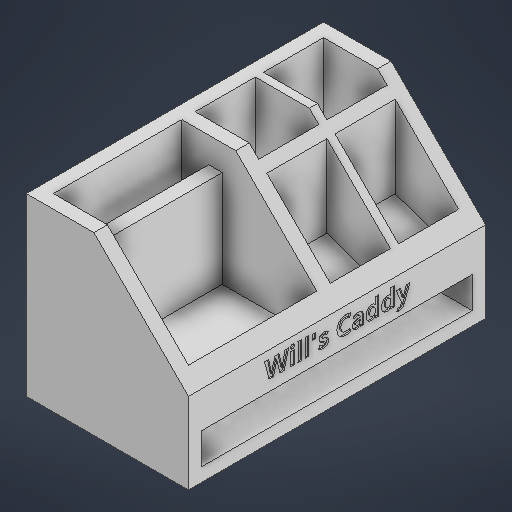
# Autodesk Inventor part: oldcaddy
Saved by Autodesk Inventor 2027.1 (Build 311270010, 270A)
## iProperties
Created: 2026-09-24
Part Number: oldcaddy
Material: Generic
Document SubType Name: Modeling
Designer: wh29971
Density: 1 g/cm^3
Appearance: Default
Author: wh29971
Autodesk Inventor part; units mm, degrees
ref_plane "YZ Plane" through (0, 0, 0) normal (1, 0, 0) x (0, 1, 0)
ref_plane "XZ Plane" through (0, 0, 0) normal (0, 1, 0) x (-1, 0, 0)
ref_plane "XY Plane" through (0, 0, 0) normal (0, 0, 1) x (1, 0, 0)
sketch "Sketch1" plane through (0, 0, 0) normal (0, 1, 0) x (-1, 0, 0)
  line L0 (-60, -110) -> (60, -110)
  line L1 (60, -110) -> (60, 110)
  line L2 (60, 110) -> (-60, 110)
  line L3 (-60, 110) -> (-60, -110)
  line L4 (-60, -110) -> (60, 110) construction
  line L5 (60, -110) -> (-60, 110) construction
  point P0 (0, 0)
  dimension "d0" = 120
  dimension "d1" = 220
  constraints: 12 end point, 2 midpoint, 2 parallel, 1 horizontal, 1 perpendicular
  measures "d0" distance of L1.end L2.end
  measures "d1" distance of L2.end L0.start
extrude "Extrusion1" add sketch "Sketch1" along normal blind 10
sketch "Sketch2" plane through (0, 10, 0) normal (0, 1, 0) x (1, 0, 0)
  point P0 (0, 0)
sketch "Sketch3" plane through (0, 10, 0) normal (0, 1, 0) x (1, 0, 0)
  line L0 (-60, 110) -> (-60, -110) projected
  line L1 (60, -110) -> (60, 110) projected
  line L2 (60, 100) -> (-50, 100)
  line L3 (-50, 100) -> (-50, -100)
  line L4 (-50, -100) -> (60, -100)
  line L5 (60, -100) -> (60, -110)
  line L6 (-60, -110) -> (60, -110) projected
  line L7 (-50, -100) -> (-50, -110)
  line L8 (-50, 100) -> (-50, 110)
  line L9 (60, 110) -> (-60, 110) projected
  point P0 (0, 0)
  dimension "d4" = 10
  dimension "d5" = 10
  constraints: 12 end point, 4 point on line, 3 perpendicular, 2 vertical, 1 collinear, 1 horizontal
  measures "d4" distance between parallel lines of L0 L3
  measures "d5" distance between parallel lines of L6 L4
extrude "Extrusion2" add sketch "Sketch3" along normal blind 120 contours L9 L8 L3 L7 L6 L0 | L9 L1 L2 L8 | L7 L4 L1 L6
chamfer "Chamfer1" distance 70 angle 45 2 edges at (60, 130, 105) (60, 130, -105)
sketch "Sketch4" plane through (-50, 10, 100) normal (1, 0, 0) x (0, 0, -1)
  line L0 (200, 0) -> (200, 50) projected
  line L1 (200, 29.3572) -> (0, 29.3572)
  line L2 (0, 0) -> (0, 50) projected
  line L3 (0, 23.1542) -> (200, 23.1542)
  point P0 (100, -10)
  constraints: 4 end point, 4 point on line, 1 horizontal, 1 perpendicular
extrude "Extrusion3" add sketch "Sketch4" along normal up to surface (110 mm away)
sketch "Sketch5" plane through (-50, 39.3572, 100) normal (0, 1, 0) x (1, 0, 0)
  line L0 (0, 0) -> (110, 0) projected
  line L1 (100, 0) -> (100, 200)
  line L2 (40, 200) -> (110, 200) projected
  line L3 (110, 0) -> (110, 200) projected
  point P0 (50, 100)
  dimension "d13" = 10
  constraints: 2 end point, 2 point on line, 1 vertical
  measures "d13" distance between parallel lines of L3 L1
extrude "Extrusion4" add sketch "Sketch5" along normal up to surface (20.6428 mm away)
sketch "Sketch6" plane through (-10, 130, 100) normal (0, 0, -1) x (-1, 0, 0)
  line L0 (-60, -70) -> (-60, -60)
  line L1 (-70, -70) -> (0, 0) projected
  line L2 (-60, -60) -> (-70, -70)
  line L3 (-70, -70) -> (-60, -70) projected
  line L4 (-70, -70) -> (-60, -70)
  point P0 (-10, -130)
  constraints: 6 end point, 1 collinear, 1 horizontal, 1 point on line, 1 vertical
extrude "Extrusion5" add sketch "Sketch6" along normal up to surface (200 mm away)
sketch "Sketch7" plane through (-50, 39.3572, 100) normal (0, 1, 0) x (1, 0, 0)
  line L0 (0, 0) -> (0, 200) projected
  line L1 (0, 100) -> (100, 100)
  line L2 (0, 95) -> (100, 95)
  line L3 (100, 0) -> (100, 200) projected
  line L4 (0, 105) -> (100, 105)
  line L5 (100, 0) -> (100, 200) projected
  line L6 (100, 95) -> (100, 100)
  line L7 (100, 100) -> (100, 105)
  line L8 (100, 95) -> (100, 100)
  point P0 (50, 100)
  dimension "d19" = 10
  constraints: 12 end point, 4 point on line, 3 collinear, 3 perpendicular, 2 horizontal, 1 midpoint, 1 other
  measures "d19" diameter of L4 L1
extrude "Extrusion6" add sketch "Sketch7" along normal up to surface (90.6428 mm away)
sketch "Sketch8" plane through (-50, 39.3572, 5) normal (0, 0, 1) x (1, 0, 0)
  line L0 (40, 90.6428) -> (110, 20.6428) projected
  line L1 (40, 90.6428) -> (110, 20.6428)
  line L2 (0, 90.6428) -> (100, 90.6428) projected
  line L3 (100, 30.6428) -> (100, 90.6428)
  line L4 (100, 90.6428) -> (40, 90.6428)
  point P0 (50, -39.3572)
  constraints: 6 end point, 1 collinear, 1 perpendicular, 1 point on line, 1 vertical
extrude "Extrusion7" cut sketch "Sketch8" against normal blind 10
sketch "Sketch9" plane through (-50, 39.3572, -100) normal (0, 1, 0) x (1, 0, 0)
  line L0 (100, -105) -> (0, -105) projected
  line L1 (30, -200) -> (30, -103.9519)
  line L2 (100, -200) -> (0, -200) projected
  line L3 (20, -200) -> (20, -103.3004)
  line L4 (20, -105) -> (30, -105)
  line L5 (20, -200) -> (30, -200)
  line L6 (0, -200) -> (0, -105) projected
  point P0 (50, -100)
  dimension "d25" = 10
  dimension "d26" = 20
  constraints: 8 end point, 5 point on line, 2 perpendicular, 1 parallel
  measures "d25" distance between parallel lines of L3 L1
  measures "d26" distance between parallel lines of L6 L3
extrude "Extrusion8" add sketch "Sketch9" along normal blind 71.643 contours L0 L1 L2 L3
sketch "Sketch13" plane through (-50, 39.3572, -100) normal (0, 1, 0) x (1, 0, 0)
  line L0 (0, 0) -> (0, -200) projected
  line L1 (0, -50.5) -> (47, -50.5)
  line L2 (100, -95) -> (100, 0) projected
  line L3 (47, -50.5) -> (47, -95)
  line L4 (40, -95) -> (100, -95) projected
  line L5 (53, -95) -> (53, -50.5)
  line L6 (53, -50.5) -> (100, -50.5)
  line L7 (100, -44.5) -> (53, -44.5)
  line L8 (53, -44.5) -> (53, 0)
  line L9 (47, -44.5) -> (47, 0)
  line L10 (110, 0) -> (0, 0) projected
  line L11 (47, -44.5) -> (0, -44.5)
  line L12 (53, -50.5) -> (53, -44.5) construction
  line L13 (0, -95) -> (0, 0) projected
  line L14 (0, -47.5) -> (100, -47.5)
  line L15 (47, -47.5) -> (47, -44.5) construction
  line L16 (47, -47.5) -> (47, -50.5) construction
  line L17 (0, -95) -> (100, -95) projected
  line L18 (50, -95) -> (50, 0) construction
  line L19 (40, 0) -> (100, 0) projected
  line L20 (47, -50.5) -> (50, -50.5) construction
  line L21 (50, -50.5) -> (53, -50.5) construction
  point P0 (50, -100)
  point P1 (0, -44.5)
  dimension "d39" = 3
  dimension "d40" = 3
  dimension "d41" = 47.5
  constraints: 30 end point, 9 perpendicular, 8 point on line, 6 equal length, 5 vertical, 3 horizontal, 3 midpoint
  measures "d39" distance between parallel lines of L14 L1
  measures "d40" distance of L20.end L5.end
  measures "d41" distance between parallel lines of L17 L14
extrude "Extrusion11" add sketch "Sketch13" along normal up to surface (90.6428 mm away) contours L11 L9 L10 L8 L7 L2 L14 L0 | L14 L2 L6 L5 L4 L3 L1 L0
sketch "Sketch15" plane through (60, 0, -110) normal (0, 0, -1) x (-1, 0, 0)
  line L0 (70, 130) -> (0, 130)
  line L1 (0, 130) -> (0, 60)
  line L2 (0, 60) -> (70, 130)
  line L3 (0, 60) -> (70, 130) projected
  point P0 (60, 0)
  constraints: 6 end point, 1 collinear, 1 horizontal, 1 perpendicular
extrude "Extrusion12" cut sketch "Sketch15" against normal up to surface (115 mm away)
sketch "Sketch16" plane through (50, 39.3572, -5) normal (0, 0, -1) x (-1, 0, 0)
  line L0 (47, 0) -> (0, 0) projected
  line L1 (0, 0) -> (100, 36.397)
  line L2 (100, 90.6428) -> (100, 0) projected
  line L3 (100, 36.397) -> (100, 0)
  line L4 (100, 0) -> (0, 0)
  point P0 (50, -39.3572)
  point P1 (47, 0)
  dimension "d47" = 20
  constraints: 6 end point, 2 collinear, 1 point on line
  measures "d47" angle of L0 L1
extrude "Extrusion13" add sketch "Sketch16" along normal up to surface (95 mm away)
sketch "Sketch17" plane through (60, 0, 110) normal (1, 0, 0) x (0, 0, -1)
  line L0 (30, 55) -> (190, 55) construction
  line L1 (190, 55) -> (190, 38.1542) construction
  line L2 (190, 38.1542) -> (30, 38.1542) construction
  line L3 (30, 38.1542) -> (30, 55) construction
  line L4 (0, 60) -> (220, 60) projected
  line L5 (210, 33.1542) -> (10, 33.1542) projected
  line L6 (190, 38.1542) -> (220, 38.1542) construction
  line L7 (220, 0) -> (220, 130) projected
  line L8 (30, 38.1542) -> (0, 38.1542) construction
  line L9 (0, 0) -> (0, 60) projected
  line L10 (74.1796, 53.8926) -> (70.7985, 41.1926)
  line L11 (70.7985, 41.1926) -> (67.7354, 41.1926)
  line L12 (67.7354, 41.1926) -> (65.5912, 49.4158)
  spline S0 degree 2 poles (65.5912, 49.4158) (65.5088, 49.7339) (65.4027, 50.4525) (65.3792, 50.8413) knots 0 0 0 1 2 2 2
  line L13 (65.3792, 50.8413) -> (65.3438, 50.8413)
  spline S1 degree 2 poles (65.3438, 50.8413) (65.3085, 50.4172) (65.2025, 49.6985) (65.12, 49.4158) knots 0 0 0 1 2 2 2
  line L14 (65.12, 49.4158) -> (62.9169, 41.1926)
  line L15 (62.9169, 41.1926) -> (59.7243, 41.1926)
  line L16 (59.7243, 41.1926) -> (56.3549, 53.8926)
  line L17 (56.3549, 53.8926) -> (59.3826, 53.8926)
  line L18 (59.3826, 53.8926) -> (61.2322, 45.3513)
  spline S2 degree 2 poles (61.2322, 45.3513) (61.3029, 45.0686) (61.3736, 44.3499) (61.409, 43.9022) knots 0 0 0 1 2 2 2
  line L19 (61.409, 43.9022) -> (61.4561, 43.9022)
  spline S3 degree 2 poles (61.4561, 43.9022) (61.4796, 44.2439) (61.6092, 44.9861) (61.7153, 45.3866) knots 0 0 0 1 2 2 2
  line L20 (61.7153, 45.3866) -> (64.0597, 53.8926)
  line L21 (64.0597, 53.8926) -> (67.0167, 53.8926)
  line L22 (67.0167, 53.8926) -> (69.1256, 45.2806)
  spline S4 degree 2 poles (69.1256, 45.2806) (69.1845, 45.045) (69.2905, 44.3617) (69.3376, 43.9258) knots 0 0 0 1 2 2 2
  line L23 (69.3376, 43.9258) -> (69.373, 43.9258)
  spline S5 degree 2 poles (69.373, 43.9258) (69.3847, 44.2674) (69.4908, 44.9625) (69.5615, 45.3277) knots 0 0 0 1 2 2 2
  line L24 (69.5615, 45.3277) -> (71.3757, 53.8926)
  line L25 (71.3757, 53.8926) -> (74.1796, 53.8926)
  line L26 (78.4208, 41.1926) -> (75.723, 41.1926)
  line L27 (75.723, 41.1926) -> (75.723, 50.7588)
  line L28 (75.723, 50.7588) -> (78.4208, 50.7588)
  line L29 (78.4208, 50.7588) -> (78.4208, 41.1926)
  spline S6 degree 2 poles (77.0896, 52.0076) (76.3827, 52.0076) (75.4756, 52.8676) (75.4756, 53.5038) knots 0 0 0 1 2 2 2
  spline S7 degree 2 poles (75.4756, 53.5038) (75.4756, 54.1635) (76.3827, 55) (77.0896, 55) knots 0 0 0 1 2 2 2
  spline S8 degree 2 poles (77.0896, 55) (77.8082, 55) (78.6918, 54.1635) (78.6918, 53.5038) knots 0 0 0 1 2 2 2
  spline S9 degree 2 poles (78.6918, 53.5038) (78.6918, 52.8441) (77.8082, 52.0076) (77.0896, 52.0076) knots 0 0 0 1 2 2 2
  line L30 (81.1187, 41.1926) -> (81.1187, 54.623)
  line L31 (81.1187, 54.623) -> (83.8283, 54.623)
  line L32 (83.8283, 54.623) -> (83.8283, 41.1926)
  line L33 (83.8283, 41.1926) -> (81.1187, 41.1926)
  line L34 (86.3966, 41.1926) -> (86.3966, 54.623)
  line L35 (86.3966, 54.623) -> (89.1063, 54.623)
  line L36 (89.1063, 54.623) -> (89.1063, 41.1926)
  line L37 (89.1063, 41.1926) -> (86.3966, 41.1926)
  line L38 (94.0897, 49.9813) -> (92.0162, 49.9813)
  line L39 (92.0162, 49.9813) -> (92.0162, 53.8808)
  line L40 (92.0162, 53.8808) -> (94.0897, 53.8926)
  line L41 (94.0897, 53.8926) -> (94.0897, 49.9813)
  line L42 (96.2103, 42.0055) -> (97.3295, 43.8787)
  spline S10 degree 2 poles (97.3295, 43.8787) (97.8007, 43.4781) (99.0848, 42.9244) (99.8624, 42.9244) knots 0 0 0 1 2 2 2
  spline S11 degree 2 poles (99.8624, 42.9244) (100.4632, 42.9244) (101.2054, 43.3956) (101.2054, 43.8904) knots 0 0 0 1 2 2 2
  spline S12 degree 2 poles (101.2054, 43.8904) (101.2054, 44.2557) (100.6282, 44.6916) (99.8388, 44.8565) knots 0 0 0 1 2 2 2
  spline S13 degree 2 poles (99.8388, 44.8565) (98.107, 45.2453) (96.599, 46.6119) (96.599, 47.8489) knots 0 0 0 1 2 2 2
  spline S14 degree 2 poles (96.599, 47.8489) (96.599, 49.2862) (98.8256, 50.9944) (100.4514, 50.9944) knots 0 0 0 1 2 2 2
  spline S15 degree 2 poles (100.4514, 50.9944) (101.2879, 50.9944) (102.7723, 50.5585) (103.4321, 50.1109) knots 0 0 0 1 2 2 2
  line L43 (103.4321, 50.1109) -> (102.4189, 48.379)
  spline S16 degree 2 poles (102.4189, 48.379) (101.8534, 48.7325) (100.8756, 49.0623) (100.3572, 49.0623) knots 0 0 0 1 2 2 2
  spline S17 degree 2 poles (100.3572, 49.0623) (99.7446, 49.0623) (99.0141, 48.5558) (99.0141, 48.167) knots 0 0 0 1 2 2 2
  spline S18 degree 2 poles (99.0141, 48.167) (99.0141, 47.7546) (99.6739, 47.3659) (100.6164, 47.1656) knots 0 0 0 1 2 2 2
  spline S19 degree 2 poles (100.6164, 47.1656) (102.2186, 46.8239) (103.6323, 45.4102) (103.6323, 44.185) knots 0 0 0 1 2 2 2
  spline S20 degree 2 poles (103.6323, 44.185) (103.6323, 42.7359) (101.5, 40.9805) (99.7446, 40.9805) knots 0 0 0 1 2 2 2
  spline S21 degree 2 poles (99.7446, 40.9805) (98.7903, 40.9805) (97.0585, 41.4871) (96.2103, 42.0055) knots 0 0 0 1 2 2 2
  spline S22 degree 2 poles (120.2083, 41.8641) (119.2069, 41.4046) (117.3219, 40.9805) (116.2263, 40.9805) knots 0 0 0 1 2 2 2
  spline S23 degree 2 poles (116.2263, 40.9805) (113.2692, 40.9805) (109.8645, 44.3028) (109.8645, 47.3894) knots 0 0 0 1 2 2 2
  spline S24 degree 2 poles (109.8645, 47.3894) (109.8645, 50.2876) (113.5756, 54.1046) (116.6151, 54.1046) knots 0 0 0 1 2 2 2
  spline S25 degree 2 poles (116.6151, 54.1046) (117.64, 54.1046) (119.2658, 53.7983) (120.1258, 53.4567) knots 0 0 0 1 2 2 2
  line L44 (120.1258, 53.4567) -> (119.2658, 51.2301)
  spline S26 degree 2 poles (119.2658, 51.2301) (118.6296, 51.4892) (117.4044, 51.7249) (116.6975, 51.7249) knots 0 0 0 1 2 2 2
  spline S27 degree 2 poles (116.6975, 51.7249) (115.0953, 51.7249) (112.7744, 49.4865) (112.7744, 47.5897) knots 0 0 0 1 2 2 2
  spline S28 degree 2 poles (112.7744, 47.5897) (112.7744, 45.6223) (114.8126, 43.4074) (116.568, 43.4074) knots 0 0 0 1 2 2 2
  spline S29 degree 2 poles (116.568, 43.4074) (117.0745, 43.4074) (118.4647, 43.7255) (119.1951, 44.0789) knots 0 0 0 1 2 2 2
  line L45 (119.1951, 44.0789) -> (120.2083, 41.8641)
  line L46 (129.5978, 41.1926) -> (127.0295, 41.1926)
  line L47 (127.0295, 41.1926) -> (127.0295, 42.5945)
  line L48 (127.0295, 42.5945) -> (126.9942, 42.5945)
  spline S30 degree 2 poles (126.9942, 42.5945) (126.5347, 41.7934) (125.1328, 40.9805) (124.2492, 40.9805) knots 0 0 0 1 2 2 2
  spline S31 degree 2 poles (124.2492, 40.9805) (123.0004, 40.9805) (121.3039, 42.5003) (121.3039, 43.8551) knots 0 0 0 1 2 2 2
  spline S32 degree 2 poles (121.3039, 43.8551) (121.3039, 45.1864) (123.0004, 46.8475) (124.7676, 47.0949) knots 0 0 0 1 2 2 2
  line L49 (124.7676, 47.0949) -> (127.0531, 47.413)
  line L50 (127.0531, 47.413) -> (127.0531, 47.6015)
  spline S33 degree 2 poles (127.0531, 47.6015) (127.0531, 48.3555) (126.1695, 49.1212) (125.392, 49.1212) knots 0 0 0 1 2 2 2
  spline S34 degree 2 poles (125.392, 49.1212) (124.7911, 49.1212) (123.4245, 48.7207) (122.7295, 48.2848) knots 0 0 0 1 2 2 2
  line L51 (122.7295, 48.2848) -> (121.7634, 49.8635)
  spline S35 degree 2 poles (121.7634, 49.8635) (122.6705, 50.4525) (124.5437, 50.9944) (125.6394, 50.9944) knots 0 0 0 1 2 2 2
  spline S36 degree 2 poles (125.6394, 50.9944) (127.6657, 50.9944) (129.5978, 48.9917) (129.5978, 46.9653) knots 0 0 0 1 2 2 2
  line L52 (129.5978, 46.9653) -> (129.5978, 41.1926)
  line L53 (127.0531, 45.1157) -> (127.0531, 45.8225)
  line L54 (127.0531, 45.8225) -> (125.2859, 45.5869)
  spline S37 degree 2 poles (125.2859, 45.5869) (124.5437, 45.4691) (123.8133, 44.7622) (123.8133, 44.1732) knots 0 0 0 1 2 2 2
  spline S38 degree 2 poles (123.8133, 44.1732) (123.8133, 43.6195) (124.532, 42.9244) (125.1328, 42.9244) knots 0 0 0 1 2 2 2
  spline S39 degree 2 poles (125.1328, 42.9244) (125.981, 42.9244) (127.0531, 44.1732) (127.0531, 45.1157) knots 0 0 0 1 2 2 2
  spline S40 degree 2 poles (138.2569, 42.5592) (137.7621, 41.7699) (136.313, 40.9805) (135.347, 40.9805) knots 0 0 0 1 2 2 2
  spline S41 degree 2 poles (135.347, 40.9805) (133.6152, 40.9805) (131.471, 43.5135) (131.471, 45.7636) knots 0 0 0 1 2 2 2
  spline S42 degree 2 poles (131.471, 45.7636) (131.471, 48.1316) (133.8272, 50.9944) (135.724, 50.9944) knots 0 0 0 1 2 2 2
  spline S43 degree 2 poles (135.724, 50.9944) (136.6311, 50.9944) (137.9035, 50.3229) (138.2569, 49.6514) knots 0 0 0 1 2 2 2
  line L55 (138.2569, 49.6514) -> (138.2923, 49.6514)
  line L56 (138.2923, 49.6514) -> (138.2923, 54.623)
  line L57 (138.2923, 54.623) -> (141.0137, 54.623)
  line L58 (141.0137, 54.623) -> (141.0137, 41.1926)
  line L59 (141.0137, 41.1926) -> (138.2923, 41.1926)
  line L60 (138.2923, 41.1926) -> (138.2923, 42.5592)
  line L61 (138.2923, 42.5592) -> (138.2569, 42.5592)
  spline S44 degree 2 poles (134.2278, 45.8579) (134.2278, 44.5266) (135.3234, 43.0658) (136.2777, 43.0658) knots 0 0 0 1 2 2 2
  spline S45 degree 2 poles (136.2777, 43.0658) (137.1966, 43.0658) (138.3512, 44.5855) (138.3512, 45.8108) knots 0 0 0 1 2 2 2
  line L62 (138.3512, 45.8108) -> (138.3512, 46.6354)
  spline S46 degree 2 poles (138.3512, 46.6354) (138.3512, 47.6133) (137.2437, 48.9092) (136.3602, 48.9092) knots 0 0 0 1 2 2 2
  spline S47 degree 2 poles (136.3602, 48.9092) (135.3705, 48.9092) (134.2278, 47.2834) (134.2278, 45.8579) knots 0 0 0 1 2 2 2
  spline S48 degree 2 poles (149.8024, 42.5592) (149.3076, 41.7699) (147.8585, 40.9805) (146.8924, 40.9805) knots 0 0 0 1 2 2 2
  spline S49 degree 2 poles (146.8924, 40.9805) (145.1606, 40.9805) (143.0165, 43.5135) (143.0165, 45.7636) knots 0 0 0 1 2 2 2
  spline S50 degree 2 poles (143.0165, 45.7636) (143.0165, 48.1316) (145.3727, 50.9944) (147.2694, 50.9944) knots 0 0 0 1 2 2 2
  spline S51 degree 2 poles (147.2694, 50.9944) (148.1766, 50.9944) (149.4489, 50.3229) (149.8024, 49.6514) knots 0 0 0 1 2 2 2
  line L63 (149.8024, 49.6514) -> (149.8377, 49.6514)
  line L64 (149.8377, 49.6514) -> (149.8377, 54.623)
  line L65 (149.8377, 54.623) -> (152.5591, 54.623)
  line L66 (152.5591, 54.623) -> (152.5591, 41.1926)
  line L67 (152.5591, 41.1926) -> (149.8377, 41.1926)
  line L68 (149.8377, 41.1926) -> (149.8377, 42.5592)
  line L69 (149.8377, 42.5592) -> (149.8024, 42.5592)
  spline S52 degree 2 poles (145.7732, 45.8579) (145.7732, 44.5266) (146.8689, 43.0658) (147.8231, 43.0658) knots 0 0 0 1 2 2 2
  spline S53 degree 2 poles (147.8231, 43.0658) (148.7421, 43.0658) (149.8966, 44.5855) (149.8966, 45.8108) knots 0 0 0 1 2 2 2
  line L70 (149.8966, 45.8108) -> (149.8966, 46.6354)
  spline S54 degree 2 poles (149.8966, 46.6354) (149.8966, 47.6133) (148.7892, 48.9092) (147.9056, 48.9092) knots 0 0 0 1 2 2 2
  spline S55 degree 2 poles (147.9056, 48.9092) (146.916, 48.9092) (145.7732, 47.2834) (145.7732, 45.8579) knots 0 0 0 1 2 2 2
  line L71 (163.8454, 50.7588) -> (159.6749, 39.6139)
  spline S56 degree 2 poles (159.6749, 39.6139) (159.2037, 38.3298) (157.3187, 36.9278) (155.9874, 36.9278) knots 0 0 0 1 2 2 2
  spline S57 degree 2 poles (155.9874, 36.9278) (155.5751, 36.9278) (154.774, 37.0221) (154.397, 37.1281) knots 0 0 0 1 2 2 2
  line L72 (154.397, 37.1281) -> (154.8682, 39.1309)
  spline S58 degree 2 poles (154.8682, 39.1309) (155.0803, 39.0484) (155.4926, 38.9777) (155.74, 38.9777) knots 0 0 0 1 2 2 2
  spline S59 degree 2 poles (155.74, 38.9777) (156.1877, 38.9777) (156.871, 39.4372) (157.0831, 39.932) knots 0 0 0 1 2 2 2
  line L73 (157.0831, 39.932) -> (157.6721, 41.3575)
  line L74 (157.6721, 41.3575) -> (153.914, 50.7588)
  line L75 (153.914, 50.7588) -> (156.9064, 50.7588)
  line L76 (156.9064, 50.7588) -> (158.7324, 44.8447)
  spline S60 degree 2 poles (158.7324, 44.8447) (158.8149, 44.6091) (158.9327, 44.0083) (158.9798, 43.6548) knots 0 0 0 1 2 2 2
  line L77 (158.9798, 43.6548) -> (159.0152, 43.6548)
  spline S61 degree 2 poles (159.0152, 43.6548) (159.0623, 43.914) (159.2037, 44.4913) (159.3097, 44.8329) knots 0 0 0 1 2 2 2
  line L78 (159.3097, 44.8329) -> (161.1593, 50.7588)
  line L79 (161.1593, 50.7588) -> (163.8454, 50.7588)
  point P0 (110, 0)
  dimension "d51" = 5
  dimension "d52" = 5
  dimension "d53" = 30
  constraints: 4 end point, 2 horizontal, 2 point on line, 1 collinear, 2 other
  measures "d51" distance between parallel lines of L4 L0
  measures "d52" distance between parallel lines of L5 L2
  measures "d53" distance of L2.end L8.end
emboss "Emboss1" sketch "Sketch17" operation cut depth 1 direction (-1, 0, 0)
sketch "Sketch18" plane through (0, 0, 0) normal (0, -1, 0) x (1, 0, 0)
  line L0 (50, 100) -> (50, 5) projected
  circle A0 centre (50, 100) radius 5
  line L1 (-60, -110) -> (-60, 110) projected
  line L2 (-60, 110) -> (60, 110) projected
  circle A1 centre (50, -100) radius 5
  circle A2 centre (-50, 100) radius 5
  circle A3 centre (-50, -100) radius 5
  point P0 (0, 0)
  dimension "d56" = 10
  dimension "d59" = 200
  dimension "d62" = 100
  constraints: 4 centre point, 1 horizontal, 1 vertical, 6 other
  measures "d56" diameter of A0
  measures "d59" distance of L0.start A1.centre
  measures "d62" distance of L0.start A2.centre
extrude "Extrusion14" cut sketch "Sketch18" against normal blind 3
body "Solid1"
